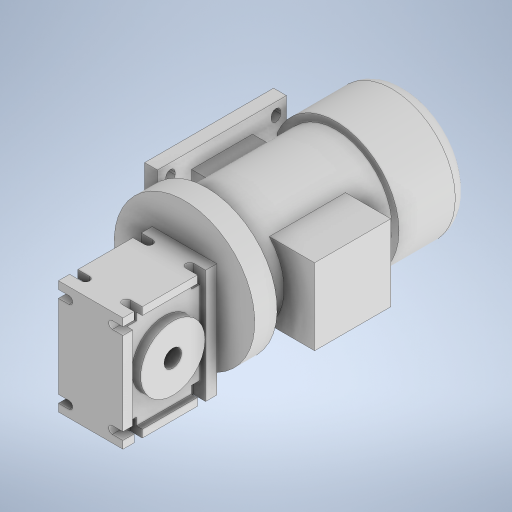
# Autodesk Inventor part: СДР 060 Мотор-редуктор
Saved by Autodesk Inventor 2024.2 (Build 282272000, 272)
## iProperties
Created: 2024-03-31
Part Number: СДР 060 Мотор-редуктор
Material: Типовые
Document SubType Name: Modeling
Designer: pokla
Density: 1 g/cm^3
Appearance: По умолчанию
Author: pokla
Autodesk Inventor part; units mm, degrees
ref_plane "YZ Plane" through (0, 0, 0) normal (1, 0, 0) x (0, 1, 0)
sketch "Эскиз1" plane through (0, 0, 0) normal (1, 0, 0) x (0, 1, 0)
  line L0 (0, 0) -> (60, 0)
  line L1 (60, 0) -> (60, -19)
  line L2 (60, -19) -> (48, -19)
  line L3 (42, -189) -> (0, -189)
  line L4 (0, -189) -> (0, 0)
  line L5 (48, -19) -> (48, -129)
  line L6 (48, -129) -> (54, -129)
  line L7 (54, -129) -> (54, -177)
  arc A0 (42, -189) -> (54, -177) centre (42, -177) ccw
  dimension "d0" = 19
  dimension "d1" = 12
  dimension "d2" = 6
  dimension "d3" = 110
  dimension "d4" = 189
  dimension "d6" = 48
  dimension "d54" = 120
  constraints: 16 end point, 5 perpendicular, 2 point on circle, 2 tangent, 1 centre point, 1 horizontal, 1 vertical
  measures "d0" distance of L0.end L1.end
  measures "d1" distance of L1.end L2.end
  measures "d2" distance of L5.end L6.end
  measures "d3" distance of L2.end L5.end
  measures "d4" distance between parallel lines of L0 L3
  measures "d6" distance of L6.end L7.end
  measures "d54" diameter of L1 L4
revolve "Вращение1" add sketch "Эскиз1" angle 360 about axis through (0, 0, -189) along (0, 0, 1)
sketch "Эскиз2" plane through (0, 0, 0) normal (1, 0, 0) x (0, 1, 0)
  line L0 (32.5, -37) -> (-32.5, -37)
  line L1 (-32.5, -37) -> (-32.5, -102)
  line L2 (-32.5, -102) -> (32.5, -102)
  line L3 (32.5, -102) -> (32.5, -37)
  line L4 (48, -19) -> (-48, -19) projected
  line L5 (48, -129) -> (-48, -129) projected
  line L6 (48, -129) -> (48, -19) projected
  line L7 (-48, -129) -> (-48, -19) projected
  point P0 (0, 0)
  point P1 (0, -37)
  point P2 (0, -19)
  dimension "d8" = 65
  dimension "d9" = 18
  constraints: 8 end point, 2 midpoint, 2 parallel, 2 perpendicular, 1 horizontal, 1 vertical alignment
  measures "d8" distance of L2.end L0.start
  measures "d9" distance between parallel lines of L0 L4
extrude "Выдавливание1" add sketch "Эскиз2" along normal blind 74 contours L3 L2 L1 L0
sketch "Эскиз3" plane through (0, 0, 0) normal (1, 0, 0) x (0, 1, 0)
  line L0 (-30, -56) -> (30, -56)
  line L1 (30, -56) -> (30, -108)
  line L2 (30, -108) -> (-30, -108)
  line L3 (-30, -108) -> (-30, -56)
  line L4 (48, -19) -> (-48, -19) projected
  point P0 (0, 0)
  point P1 (0, -108)
  dimension "d13" = 60
  dimension "d14" = 52
  dimension "d15" = 37
  constraints: 8 end point, 2 parallel, 1 horizontal, 1 midpoint, 1 perpendicular, 1 vertical alignment
  measures "d13" distance of L1.end L2.end
  measures "d14" distance of L0.end L1.end
  measures "d15" distance between parallel lines of L0 L4
extrude "Выдавливание2" add sketch "Эскиз3" against normal blind 50
sketch "Эскиз5" plane through (-50, 0, 0) normal (-1, 0, 0) x (0, 0, 1)
  line L0 (-137, -44) -> (-27, -44)
  line L1 (-27, -44) -> (-27, 44)
  line L2 (-27, 44) -> (-137, 44)
  line L3 (-137, 44) -> (-137, -44)
  line L4 (-56, 30) -> (-108, 30) projected
  point P0 (0, 0)
  point P1 (-27, 0)
  point P2 (-82, 44)
  point P3 (-82, 30)
  point P4 (-108, 30)
  dimension "d20" = 110
  dimension "d21" = 88
  constraints: 6 end point, 2 horizontal, 1 horizontal alignment, 1 midpoint, 1 parallel, 1 perpendicular, 1 vertical alignment, 6 other
  measures "d20" distance of L3.start L1.end
  measures "d21" distance of L1.end L0.end
extrude "Выдавливание4" add sketch "Эскиз5" along normal blind 11
sketch "Эскиз6" plane through (-61, 0, 0) normal (-1, 0, 0) x (0, 0, 1)
  line L0 (-128, 35) -> (-128, 33) construction
  line L1 (-132, 35) -> (-132, 33)
  line L2 (-124, 33) -> (-124, 35)
  arc A0 (-124, 35) -> (-132, 35) centre (-128, 35) ccw
  arc A1 (-132, 33) -> (-124, 33) centre (-128, 33) ccw
  line L3 (-137, 44) -> (-137, -44) projected
  line L4 (-27, 44) -> (-137, 44) projected
  line L5 (-129, 48) -> (-19, 48) projected
  line L6 (-129, -48) -> (-19, -48) projected
  line L7 (-56, 30) -> (-108, 30) construction
  line L8 (-82, 30) -> (-82, -30) construction
  line L9 (-108, -30) -> (-56, -30) construction
  line L10 (-137, 44) -> (-137, -44) construction
  line L11 (-137, 0) -> (-49, 0) construction
  point P0 (0, 0)
  point P1 (-128, 34)
  point P2 (-128, 29)
  point P3 (-128, 39)
  point P4 (-132, 34)
  point P5 (-124, 34)
  dimension "d24" = 10
  dimension "d25" = 8
  dimension "d27" = 13
  dimension "d28" = 15
  constraints: 12 end point, 6 midpoint, 6 point on circle, 4 tangent, 2 centre point, 1 horizontal, 1 parallel, 1 vertical, 1 other
  measures "d24" distance of point (-128, 29) point (-128, 39)
  measures "d25" distance of point (-132, 34) point (-124, 34)
  measures "d27" distance from line of L3 point (-124, 34)
extrude "Выдавливание5" cut sketch "Эскиз6" against normal up to surface (11 mm away)
pattern_linear "Rectangular Pattern1" count 2 spacing 68 along (0, -1, 0) count 2 spacing 90 along (0, 0, 1) of "Выдавливание5"
sketch "Эскиз7" plane through (0, 0, 0) normal (0, 0, 1) x (1, 0, 0)
  line L0 (27.5, 27) -> (-27.5, 27)
  line L1 (-27.5, 27) -> (-27.5, -70)
  line L2 (-27.5, -70) -> (27.5, -70)
  line L3 (27.5, -70) -> (27.5, 27)
  line L4 (0, 0) -> (0, -221.6884) construction
  line L5 (0, 0) -> (0, -163.0687) construction
  point P0 (0, 27)
  point P1 (0, -70)
  dimension "d31" = 55
  dimension "d32" = 97
  dimension "d61" = 0
  dimension "d62" = 27
  constraints: 12 end point, 2 midpoint, 2 parallel, 2 point on line, 1 perpendicular, 1 vertical
  measures "d31" distance of L2.end L1.end
  measures "d32" distance of L1.end L0.end
  measures "d61" distance between parallel lines of L4 L5
  measures "d62" distance of L4.start point (0, 27)
extrude "Выдавливание6" add sketch "Эскиз7" along normal blind 80
sketch "Эскиз8" plane through (-27.5, -70, 0) normal (0, -1, 0) x (1, 0, 0)
  circle A0 centre (45, 67) radius 3.5
  circle A1 centre (45, 13) radius 3.5
  circle A2 centre (10, 13) radius 3.5
  circle A3 centre (10, 67) radius 3.5
  line L0 (55, 0) -> (55, 80) projected
  line L1 (0, 80) -> (55, 80) projected
  line L2 (55, 40) -> (0, 40) construction
  line L3 (0, 0) -> (0, 80) projected
  line L4 (27.5, 80) -> (27.5, 0) construction
  line L5 (87.5, 0) -> (-32.5, 0) construction
  line L6 (45, 63.5) -> (55, 63.5)
  line L7 (45, 70.5) -> (55, 70.5)
  line L8 (45, 9.5) -> (55, 9.5)
  line L9 (45, 16.5) -> (55, 16.5)
  line L10 (10, 9.5) -> (0, 9.5)
  line L11 (10, 16.5) -> (0, 16.5)
  line L12 (10, 63.5) -> (0, 63.5)
  line L13 (10, 70.5) -> (0, 70.5)
  dimension "d36" = 7
  dimension "d37" = 10
  dimension "d38" = 13
  constraints: 20 end point, 14 point on line, 8 point on circle, 6 perpendicular, 5 tangent, 4 centre point, 3 midpoint, 3 other
  measures "d36" diameter of A0
  measures "d37" distance from line of L0 A0.centre
  measures "d38" distance from line of L1 A0.centre
extrude "Выдавливание7" cut sketch "Эскиз8" against normal blind 13
ref_plane "Work Plane5" through (-27.5, -21.5, 80) normal (0, 1, 0) x (1, 0, 0)
sketch "Эскиз11" plane through (27.5, -53.3268, 0) normal (1, 0, 0) x (0, 0, -1)
  line L0 (-80, 80.3268) -> (-80, -16.6732) construction
  line L1 (-80, 31.8268) -> (0, 31.8268) construction
  line L2 (0, 0) -> (0, 80.3268) construction
  line L3 (-16.5, -16.6732) -> (-63.5, -16.6732) construction
  line L4 (-40, -16.6732) -> (-40, 80.3268) construction
  line L5 (0, 80.3268) -> (-80, 80.3268) construction
  circle A0 centre (-40, 31.8268) radius 7.5
  point P0 (0, 53.3268)
  point P1 (-80, -0.1732)
  dimension "d50" = 15
  constraints: 5 midpoint, 4 end point, 1 centre point, 1 horizontal, 1 point on line
  measures "d50" diameter of A0
extrude "Выдавливание10" cut sketch "Эскиз11" against normal through all
sketch "Sketch14" plane through (0, 0, 80) normal (0, 0, 1) x (1, 0, 0)
  line L0 (-27.5, 27) -> (-27.5, -70) projected
  line L1 (-27.5, -70) -> (27.5, -70) construction
  line L2 (27.5, -70) -> (27.5, 27) projected
  line L3 (27.5, 27) -> (-27.5, 27) construction
  line L4 (27.5, -63.5) -> (18.5, -63.5)
  arc A0 (18.5, -57) -> (18.5, -63.5) centre (18.5, -60.25) ccw
  line L5 (18.5, -57) -> (27.5, -57)
  line L6 (-27.5, -63.5) -> (-18.5, -63.5)
  arc A1 (-18.5, -63.5) -> (-18.5, -57) centre (-18.5, -60.25) ccw
  line L7 (-18.5, -57) -> (-27.5, -57)
  line L8 (0, -70) -> (0, 27) construction
  point P0 (0, 0)
  dimension "d69" = 6.5
  dimension "d70" = 6.5
  dimension "d71" = 9
  constraints: 10 end point, 6 point on line, 4 point on circle, 4 tangent, 2 centre point, 2 midpoint, 2 perpendicular, 1 other
  measures "d69" distance between parallel lines of L5 L4
  measures "d70" distance between parallel lines of L1 L4
  measures "d71" distance of L4.start L4.end
ref_plane "Work Plane6" through (0, -70, 0) normal (-1, 0, 0) x (0, 0, 1)
extrude "Extrusion15" cut sketch "Sketch14" against normal blind 13
mirror "Mirror7" about plane through (-27.5, -21.5, 80) normal (0, 1, 0) of "Extrusion15", "Выдавливание7"
sketch "Sketch17" plane through (27.5, -70, 63.5) normal (1, 0, 0) x (0, 0, -1)
  line L0 (47, 84) -> (47, 97) projected
  line L1 (47, 97) -> (0, 97) projected
  line L2 (0, 97) -> (0, 84) projected
  line L3 (0, 84) -> (-16.5, 84) projected
  line L4 (-16.5, 13) -> (-16.5, 84) projected
  line L5 (-16.5, 13) -> (0, 13) projected
  line L6 (0, 13) -> (0, 0) projected
  line L7 (47, 0) -> (0, 0) projected
  line L8 (47, 0) -> (47, 13) projected
  line L9 (47, 13) -> (54, 13) projected
  line L10 (54, 13) -> (54, 0) projected
  line L11 (63.5, 0) -> (54, 0) projected
  line L12 (63.5, 0) -> (63.5, 16.6732) projected
  line L13 (63.5, 97) -> (63.5, 16.6732) projected
  line L14 (63.5, 97) -> (54, 97) projected
  line L15 (54, 97) -> (54, 84) projected
  line L16 (54, 84) -> (47, 84) projected
  circle A0 centre (23.5, 48.5) radius 7.5 projected
  circle A1 centre (23.5, 48.5) radius 27.5
  line L17 (-8.25, 13) -> (-8.25, 84)
  line L18 (47, 90.5) -> (0, 90.5)
  line L19 (47, 13) -> (47, 0) projected
  line L20 (47, 6.5) -> (0, 6.5)
  line L21 (54, 13) -> (54, 84)
  point P0 (63.5, 70)
  point P1 (47, 6.5)
  dimension "d84" = 55
  constraints: 8 end point, 6 midpoint, 1 centre point, 1 coincident, 1 vertical
  measures "d84" diameter of A1
extrude "Extrusion16" cut sketch "Sketch17" against normal blind 5 contours L16 L21 L9 L8 L20 L6 L5 L17 L3 L2 L18 L0
sketch "Sketch18" plane through (27.5, -21.5, 40) normal (1, 0, 0) x (0, 0, -1)
  circle A0 centre (0, 0) radius 7.5 projected
  circle A1 centre (0, 0) radius 27.5 projected
  point P0 (40, 21.5)
extrude "Extrusion17" add sketch "Sketch18" along normal blind 2.5
mirror "Mirror8" about plane through (0, -70, 0) normal (-1, 0, 0) of "Extrusion16", "Extrusion17"
equation "\"d70\" = d69"
equation "\"Reductor_angle\" = 0"
